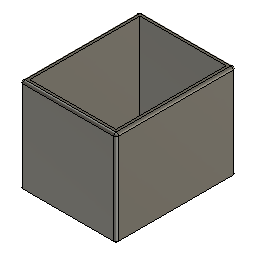
Parametric box (Autodesk Fusion 360 design; units mm, degrees)
Autodesk Fusion 360 part; units mm, degrees
sketch "Sketch1" plane through (0, 0, 0) normal (0, 0, 1) x (1, 0, 0)
  line L0 (10, -12.5) -> (-10, -12.5)
  line L1 (-10, -12.5) -> (-10, 12.5)
  line L2 (-10, 12.5) -> (10, 12.5)
  line L3 (10, 12.5) -> (10, -12.5)
  line L4 (10, -12.5) -> (-10, 12.5) construction
  line L5 (-10, -12.5) -> (10, 12.5) construction
  dimension "d5" = 20
  dimension "d6" = 25
  constraint horizontal L0
  constraint perpendicular L0 L1
  constraint parallel L0 L2
  constraint parallel L1 L3
  constraint coincident L4 origin
  constraint coincident L5 origin
  measures "d5" distance of L1.end L2.end
  measures "d6" distance of L0.end L1.end
extrude "Extrude1" add sketch "Sketch1" along normal blind 20
shell "Shell1" thickness 1 removed faces 1 at (-3.3333, 4.1667, 20)
fillet "Fillet1" radius 0.5 4 edges at (-10, 12.5, 10) (-10, -12.5, 10) (10, -12.5, 10) (10, 12.5, 10)
fillet "Fillet1" radius 0.5 4 edges at (0, 12.5, 20) (-10, 0, 20) (0, -12.5, 20) (10, 0, 20)
chamfer "Chamfer1" distance 0.5 angle 45 8 edges at (10, 0, 0) (9.8536, -12.3536, 0) (0, -12.5, 0) (-9.8536, -12.3536, 0) (-10, 0, 0) (-9.8536, 12.3536, 0) (0, 12.5, 0) (9.8536, 12.3536, 0)
fillet "Fillet2" radius 0.5 4 edges at (-9, 0, 1) (0, -11.5, 1) (9, 0, 1) (0, 11.5, 1)
equation "length = 25 mm"
equation "width = 20 mm"
equation "height = 20 mm"
equation "thickness = 1 mm"
equation "d5 = width"
equation "d6 = length"
equation "d7 = height"
equation "d9 = thickness"
named bodies: "Box"
